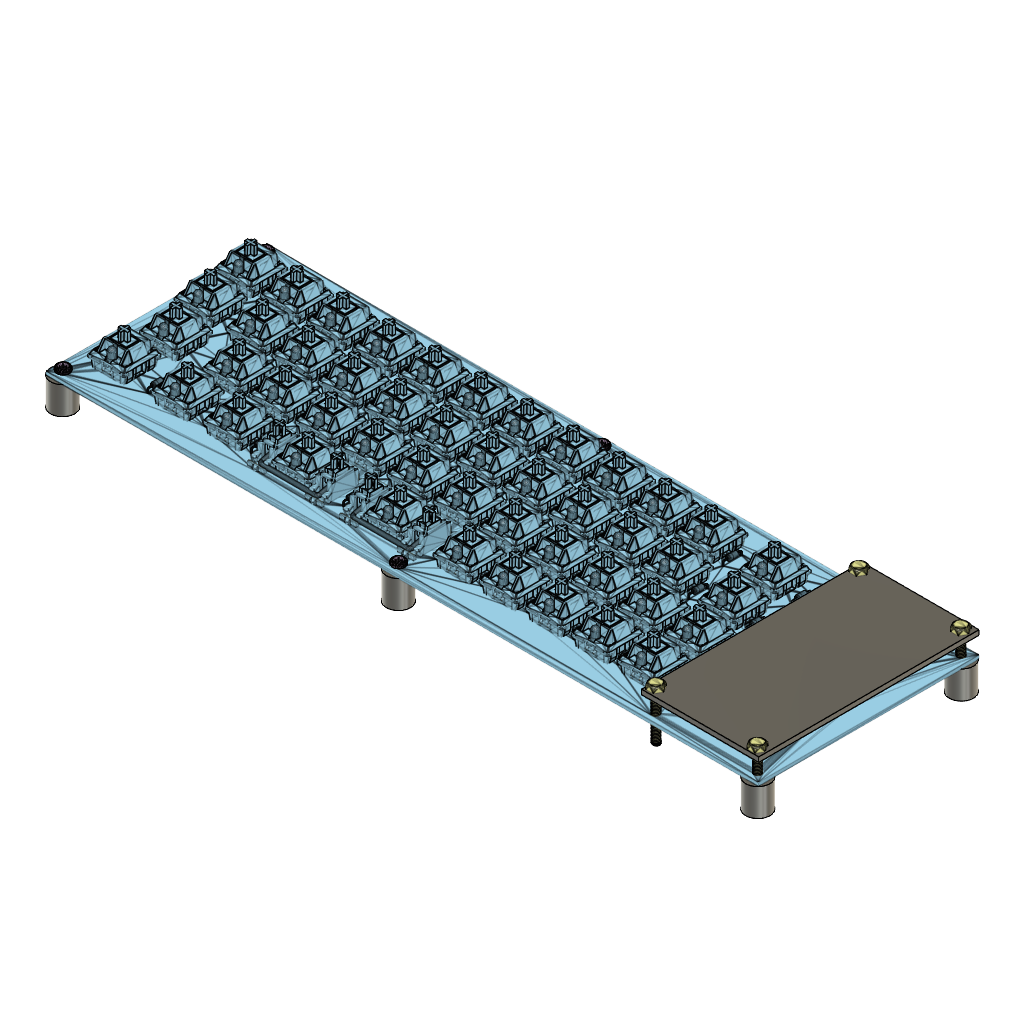
Cad model (Autodesk Fusion 360 design; units mm, degrees)
Autodesk Fusion 360 part; units mm, degrees
sketch "Sketch1" plane through (0, 0, 0) normal (0, 0, 1) x (1, 0, 0)
  line L0 (148.9838, 40.26) -> (112.2, 40.26)
  line L1 (112.2, 40.26) -> (112.2, -50.9)
  line L2 (112.2, -50.9) -> (148.9838, -50.9)
  line L3 (148.9838, -50.9) -> (148.9838, 40.26)
  circle A0 centre (114.57, 36.7) radius 1.475
  circle A1 centre (145.38, 36.7) radius 1.475
  circle A2 centre (114.5828, -47.4582) radius 1.475
  circle A3 centre (145.3856, -47.4675) radius 1.475
  dimension "d2" = 2.95
  dimension "d3" = 2.95
  dimension "d4" = 2.95
  dimension "d5" = 2.95
  constraint horizontal L0
  constraint vertical L1
  constraint horizontal L2
  constraint vertical L3
  measures "d2" diameter of A0
  measures "d3" diameter of A1
  measures "d4" diameter of A2
  measures "d5" diameter of A3
extrude "Extrude1" add sketch "Sketch1" along normal blind 2 makes body 1
move_body "Move1" bodies 1 to x (1, 0, 0) y (0, 1, 0) z (0, 0, 1) at (0, 0, 9)
sketch "Sketch2" plane through (0, 0, 0) normal (0, 0, 1) x (1, 0, 0)
  circle A0 centre (0.5, 52.5) radius 1.475
  circle A1 centre (0.5, 52.5) radius 5
  dimension "d8" = 2.95
  dimension "d9" = 10
  constraint concentric A0 A1
  measures "d8" diameter of A0
  measures "d9" diameter of A1
extrude "Extrude2" add sketch "Sketch2" along normal blind 18.5 separate body makes body 2
extrude "Extrude3" add sketch "Sketch2" against normal blind 2 contours A0 | A1 bodies 2
move_body "Move2" bodies 1 to x (1, 0, 0) y (0, 1, 0) z (0, 0, 1) at (0, 0, 20)
move_body "Move3" bodies 2 to x (1, 0, 0) y (0, 1, 0) z (0, 0, 1) at (7.7, -15.8, 0)
move_body "Move4" bodies 2 to x (1, 0, 0) y (0, 1, 0) z (0, 0, 1) at (0, 0, 1.5)
extrude "Extrude4" cut 1 faces at (12.0009, 36.3783, 20) along direction (0, 0, -1) blind 10 on bodies 2 bodies 2
move_body "Move5" bodies 2 to x (1, 0, 0) y (0, 1, 0) z (0, 0, 1) at (0, 0, 0.5)
copy_body "CopyPasteBodies2" bodies 2 makes body 3
move_body "Move6" bodies 3 to x (1, 0, 0) y (0, 1, 0) z (0, 0, 1) at (137.2, 0, 0)
copy_body "CopyPasteBodies3" bodies 3 makes body 4
move_body "Move7" bodies 4 to x (1, 0, 0) y (0, 1, 0) z (0, 0, 1) at (0, -84.2, 0)
copy_body "CopyPasteBodies4" bodies 4 makes body 5
move_body "Move8" bodies 5 to x (1, 0, 0) y (0, 1, 0) z (0, 0, 1) at (-137.2, 0, 0)
copy_body "CopyPasteBodies5" bodies 5 makes body 6
move_body "Move9" bodies 6 to x (1, 0, 0) y (0, 1, 0) z (0, 0, 1) at (-138.9, 0, 0)
copy_body "CopyPasteBodies6" bodies 6 makes body 7
move_body "Move10" bodies 7 to x (1, 0, 0) y (0, 1, 0) z (0, 0, 1) at (0, 84.15, 0)
move_body "Move11" bodies 1 to x (1, 0, 0) y (0, 1, 0) z (0, 0, 1) at (0, 0, -10)
extrude "Extrude5" add 1 faces at (149.2064, -47.7484, 10.5) along direction (0, 0, 1) blind 1 on bodies 4 bodies 4
move_body "Move12" bodies 4 to x (1, 0, 0) y (0, 1, 0) z (0, 0, 1) at (0, 0, -1)
extrude "Extrude6" add 1 faces at (149.2064, 36.4516, 10.5) along direction (0, 0, 1) blind 1 on bodies 3 bodies 3
move_body "Move13" bodies 3 to x (1, 0, 0) y (0, 1, 0) z (0, 0, 1) at (0, 0, -1)
extrude "Extrude7" add 1 faces at (12.0009, 36.3783, 10.5) along direction (0, 0, 1) blind 1 on bodies 2 bodies 2
move_body "Move14" bodies 2 to x (1, 0, 0) y (0, 1, 0) z (0, 0, 1) at (0, 0, -1)
extrude "Extrude8" add 1 faces at (-126.8936, 36.4016, 10.5) along direction (0, 0, 1) blind 1 on bodies 7 bodies 7
move_body "Move15" bodies 7 to x (1, 0, 0) y (0, 1, 0) z (0, 0, 1) at (0, 0, -1)
extrude "Extrude9" add 1 faces at (-126.8936, -47.7484, 10.5) along direction (0, 0, 1) blind 1 on bodies 6 bodies 6
move_body "Move16" bodies 6 to x (1, 0, 0) y (0, 1, 0) z (0, 0, 1) at (0, 0, -1)
extrude "Extrude10" add 1 faces at (12.0009, -47.8217, 10.5) along direction (0, 0, 1) blind 1 on bodies 5 bodies 5
move_body "Move17" bodies 5 to x (1, 0, 0) y (0, 1, 0) z (0, 0, 1) at (0, 0, -1)
other "Base Mesh Feature2"
other "CopyPasteMeshes1"
other "Modify3"
other "CopyPasteMeshes2"
other "Modify4"
other "Base Mesh Feature3"
other "MeshReduce2"
other "CopyPasteMeshes3"
other "Modify5"
other "CopyPasteMeshes4"
other "Modify6"
other "CopyPasteMeshes5"
other "Modify7"
other "CopyPasteMeshes6"
other "Modify8"
other "Base Mesh Feature4"
other "Modify9"
move_body "Move18" bodies 3 4 to x (1, 0, 0) y (0, 1, 0) z (0, 0, 1) at (11.7, -0.2, 0)
extrude "Extrude11" add 1 faces at (148.9838, -20.5133, 19.6667) along direction (-1, 0, 0) blind 6 on bodies 1 bodies 1
extrude "Extrude12" add 1 faces at (148.9838, -20.5133, 19.6667) along direction (1, 0, 0) blind 11.7 on bodies 1 bodies 1
sketch "Sketch3" plane through (0, 0, 21) normal (0, 0, 1) x (-1, 0, 0)
  line L0 (-160.6838, -40.26) -> (-112.2, -40.26)
  line L1 (-112.2, -40.26) -> (-112.2, 50.9)
  line L2 (-112.2, 50.9) -> (-160.6838, 50.9)
  line L3 (-160.6838, 50.9) -> (-160.6838, -40.26)
  circle A0 centre (-114.5828, 47.4582) radius 1.475
  circle A1 centre (-114.57, -36.7) radius 1.475
  circle A2 centre (-157.0838, -36.51) radius 1.475
  circle A3 centre (-157.0838, 47.65) radius 1.475
  dimension "d34" = 2.95
  dimension "d35" = 2.95
  dimension "d36" = 3.75
  dimension "d37" = 3.6
  dimension "d39" = 3.6
  dimension "d40" = 3.25
  measures "d34" diameter of A2
  measures "d35" diameter of A3
  measures "d36" distance of L0 A2.centre
  measures "d37" distance of L3 A2.centre
  measures "d39" distance of L3 A3.centre
  measures "d40" distance of L2 A3.centre
extrude "Extrude13" cut sketch "Sketch3" against normal blind 3 contours A2 | A3 bodies 1
other "Modify10"
other "Modify11"
